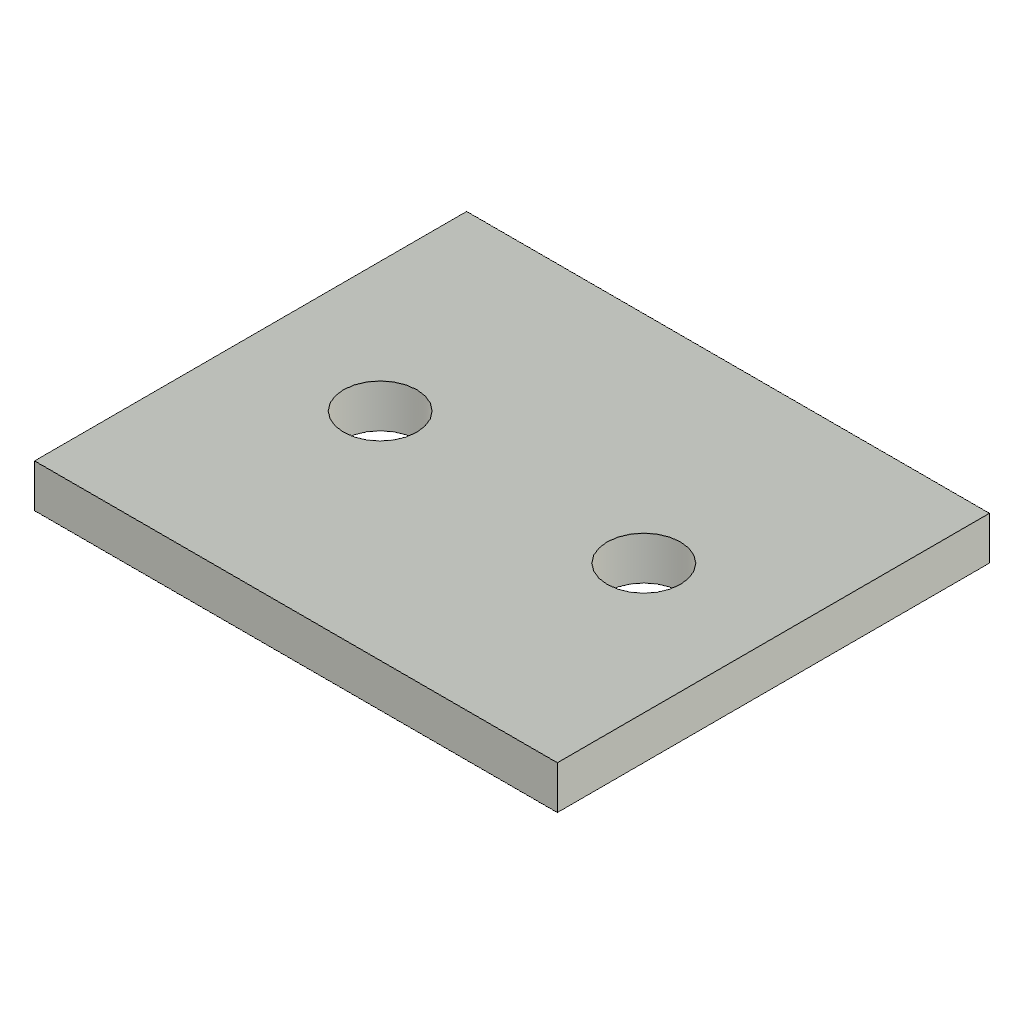
joint_plate (Autodesk Fusion 360 design; units mm, degrees)
part number: 2026-10-10-17-06-19-267
Autodesk Fusion 360 part; units mm, degrees
sketch "Flat joint plate sketch" plane through (0, 0, 0) normal (0, 0, 1) x (1, 0, 0)
  line L0 (0, -10) -> (24.2, -10)
  line L1 (24.2, -10) -> (24.2, 10)
  line L2 (24.2, 10) -> (0, 10)
  line L3 (0, 10) -> (0, -10)
extrude "Flat joint plate" add sketch "Flat joint plate sketch" along normal blind 2
ref_plane "WorkPlane1" through (0, 0, -0.05) normal (0, 0, 1) x (1, 0, 0)
sketch "Seam bolt 6 sketch" plane through (0, 0, -0.05) normal (0, 0, 1) x (1, 0, 0)
  circle A0 centre (6, 0) radius 1.7
  dimension "d360" = 3.4
  measures "d360" diameter of A0
extrude "Seam bolt 6" cut sketch "Seam bolt 6 sketch" along normal blind 2.1
ref_plane "WorkPlane2" through (0, 0, -0.05) normal (0, 0, 1) x (1, 0, 0)
sketch "Seam bolt 18.2 sketch" plane through (0, 0, -0.05) normal (0, 0, 1) x (1, 0, 0)
  circle A0 centre (18.2, 0) radius 1.7
  dimension "d365" = 3.4
  measures "d365" diameter of A0
extrude "Seam bolt 18.2" cut sketch "Seam bolt 18.2 sketch" along normal blind 2.1
equation "d360 = m3Clearance"
equation "d365 = m3Clearance"
equation "m3Clearance = 3.4 mm" comment "Root registration and tip adapter holes"
named bodies: "joint_plate - printable solid"
